Bottom Lid Link native (Autodesk Fusion 360 design; units mm, degrees)
part number: 2026-10-13-21-21-50-336
Autodesk Fusion 360 part; units mm, degrees
ref_plane "WorkPlane1" through (-15.435, 0, 0) normal (1, 0, 0) x (0, 1, 0)
sketch "Profile" plane through (-15.435, 0, 0) normal (1, 0, 0) x (0, 0, -1)
  line L0 (-2.6908, -19.8774) -> (-49.4851, -15.5433)
  arc A0 (-49.1124, -11.5607) -> (-49.4851, -15.5433) centre (-49.3006, -13.5518) ccw
  line L1 (-49.1124, -11.5607) -> (-3.2847, -15.8922)
  line L2 (-3.2847, -15.8922) -> (2.406, -13.9907)
  arc A1 (4.0015, -17.6412) -> (2.406, -13.9907) centre (3.3677, -15.7443) ccw
  line L3 (4.0015, -17.6412) -> (-2.6908, -19.8774)
  dimension "d13" = 2
  dimension "d14" = 49.3006
  dimension "d15" = 13.5518
  dimension "d16" = 3.3677
  dimension "d17" = 15.7443
  dimension "d18" = 2.6908
  dimension "d19" = 19.8774
  dimension "d20" = 49.1124
  dimension "d21" = 3.2847
  dimension "d22" = 2.406
  constraint tangent L0 A0
  constraint tangent A0 L1
  constraint tangent A1 L3
  constraint equal A0 A1
  measures "d13" radius of A0
  measures "d14" horizontal distance of origin A0.centre
  measures "d15" vertical distance of origin A0.centre
  measures "d16" horizontal distance of origin A1.centre
  measures "d17" vertical distance of origin A1.centre
  measures "d18" horizontal distance of origin L0.start
  measures "d19" vertical distance of origin L0.start
  measures "d20" horizontal distance of origin A0.start
  measures "d21" horizontal distance of origin L1.end
  measures "d22" horizontal distance of origin L2.end
extrude "Profile (1)" add sketch "Profile" along normal mid plane 2
ref_plane "WorkPlane2" through (-15.435, 0, 0) normal (1, 0, 0) x (0, 1, 0)
sketch "Hole 1" plane through (-15.435, 0, 0) normal (1, 0, 0) x (0, 0, -1)
  circle A0 centre (-49.3006, -13.5518) radius 1.25
  dimension "d23" = 2.5
  dimension "d24" = 49.3006
  dimension "d25" = 13.5518
  measures "d23" diameter of A0
  measures "d24" horizontal distance of origin A0.centre
  measures "d25" vertical distance of origin A0.centre
extrude "Hole 1 (1)" cut sketch "Hole 1" along normal mid plane 2
ref_plane "WorkPlane3" through (-15.435, 0, 0) normal (1, 0, 0) x (0, 1, 0)
sketch "Hole 2" plane through (-15.435, 0, 0) normal (1, 0, 0) x (0, 0, -1)
  circle A0 centre (3.3677, -15.7443) radius 1.25
  dimension "d26" = 2.4999
  dimension "d27" = 3.3677
  dimension "d28" = 15.7443
  measures "d26" diameter of A0
  measures "d27" horizontal distance of origin A0.centre
  measures "d28" vertical distance of origin A0.centre
extrude "Hole 2 (1)" cut sketch "Hole 2" along normal mid plane 2
named bodies: "Bottom Lid Link native"
